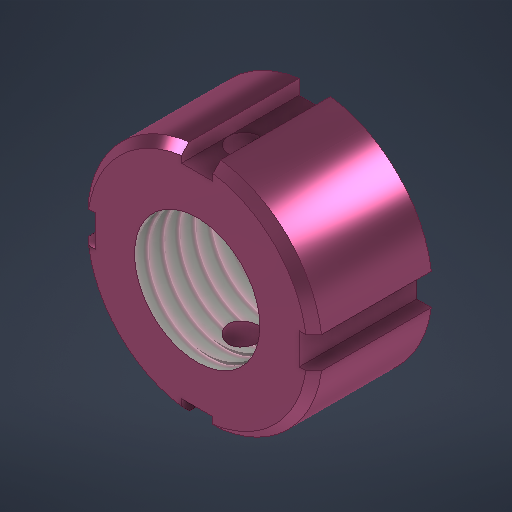
# Autodesk Inventor part: 9. Lock Nut M16
Saved by Autodesk Inventor 2025.2 (Build 292293000, 293)
## iProperties
Created: 2025-05-09
Part Number: 9. Lock Nut M16
Material: Steel, Mild
Document SubType Name: Modeling
Designer: trysm
Density: 7.85 g/cm^3
Appearance: Semi-Polished
Author: trysm
Autodesk Inventor part; units mm, degrees
ref_plane "YZ Plane" through (0, 0, 0) normal (1, 0, 0) x (0, 1, 0)
ref_plane "XZ Plane" through (0, 0, 0) normal (0, 1, 0) x (-1, 0, 0)
ref_plane "XY Plane" through (0, 0, 0) normal (0, 0, 1) x (1, 0, 0)
sketch "Sketch1" plane through (0, 0, 0) normal (0, 1, 0) x (-1, 0, 0)
  circle A0 centre (0, 0) radius 15
  circle A1 centre (0, 0) radius 8
  line L0 (2, 13) -> (-2, 13)
  line L1 (-2, 13) -> (-2, 17)
  line L2 (-2, 17) -> (2, 17)
  line L3 (2, 17) -> (2, 13)
  line L4 (2, 13) -> (-2, 17) construction
  line L5 (-2, 13) -> (2, 17) construction
  line L6 (-13, 2) -> (-13, -2)
  line L7 (-13, -2) -> (-17, -2)
  line L8 (-17, -2) -> (-17, 2)
  line L9 (-17, 2) -> (-13, 2)
  line L10 (-13, 2) -> (-17, -2) construction
  line L11 (-13, -2) -> (-17, 2) construction
  line L12 (-2, -13) -> (2, -13)
  line L13 (2, -13) -> (2, -17)
  line L14 (2, -17) -> (-2, -17)
  line L15 (-2, -17) -> (-2, -13)
  line L16 (-2, -13) -> (2, -17) construction
  line L17 (2, -13) -> (-2, -17) construction
  line L18 (13, -2) -> (13, 2)
  line L19 (13, 2) -> (17, 2)
  line L20 (17, 2) -> (17, -2)
  line L21 (17, -2) -> (13, -2)
  line L22 (13, -2) -> (17, 2) construction
  line L23 (13, 2) -> (17, -2) construction
  point P0 (0, 15)
  point P1 (-15, 0)
  point P2 (0, -15)
  point P3 (15, 0)
  point P4 (-2, 14.8661)
  point P5 (-14.8661, 2)
  point P6 (-14.8661, -2)
  point P7 (-2, -14.8661)
  point P8 (2, -14.8661)
  point P9 (14.8661, -2)
  point P10 (14.8661, 2)
  point P11 (2, 14.8661)
  dimension "d0" = 30
  dimension "d1" = 16
  dimension "d2" = 4
  dimension "d3" = 4
  dimension "d6" = 360
  constraints: 48 end point, 2 coincident, 2 midpoint, 2 parallel, 1 centre point, 1 horizontal, 1 perpendicular, 1 vertical alignment, 48 other
  measures "d1" diameter of A1
  measures "d2" distance of L1.end L2.end
  measures "d3" distance of L0.end L1.end
extrude "Extrusion1" add sketch "Sketch1" along normal blind 15 contours L19 L18 L21 A0 L13 L12 L15 L7 L6 L9 L1 L0 L3
thread "Thread1" size "M16x2" class "6H" standard "ANSI Metric M Profile" full length
sketch "Sketch2" plane through (-2, 0, 13) normal (0, 0, 1) x (1, 0, 0)
  line L0 (0, 0) -> (4, 0) projected
  line L1 (0, 0) -> (0, 15) projected
  point P0 (2, 0)
  point P1 (2, 6)
  dimension "d12" = 6
  dimension "d13" = 2
  measures "d12" distance from line of L0 point (2, 6)
  measures "d13" distance from line of L1 point (2, 6)
hole "Hole1" at (0, 6, 13) direction (0, 0, -1) diameter 4 end through all
chamfer "Chamfer1" distance 1 angle 45 4 edges at (-10.6066, 0, 10.6066) (10.6066, 0, 10.6066) (-10.6066, 0, -10.6066) (10.6066, 0, -10.6066)
body "Solid1"
